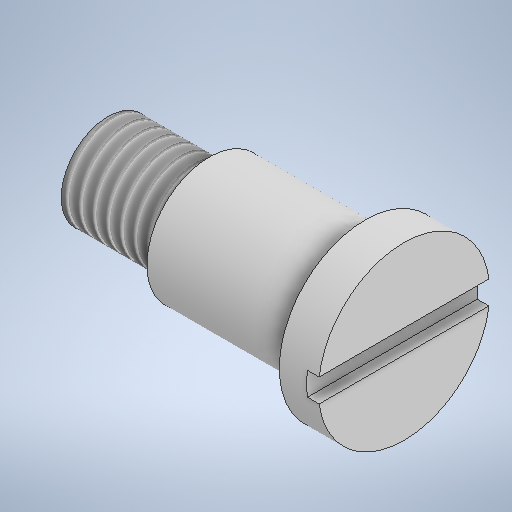
# Autodesk Inventor part: Pasador de acero
Saved by Autodesk Inventor 2025.3 (Build 293356030, 356C)
## iProperties
Created: 2025-08-17
Part Number: Pasador de acero
Material: Generic
Document SubType Name: Modeling
Designer: PC
Density: 1 g/cm^3
Appearance: Default
Author: PC
Autodesk Inventor part; units mm, degrees
ref_plane "YZ Plane" through (0, 0, 0) normal (1, 0, 0) x (0, 1, 0)
ref_plane "XZ Plane" through (0, 0, 0) normal (0, 1, 0) x (-1, 0, 0)
ref_plane "XY Plane" through (0, 0, 0) normal (0, 0, 1) x (1, 0, 0)
sketch "Sketch1" plane through (0, 0, 0) normal (0, 1, 0) x (-1, 0, 0)
  line L0 (0, 0) -> (-38, 0)
  line L1 (-38, 0) -> (-38, -11)
  line L2 (-38, -11) -> (-33, -11)
  line L3 (-33, -11) -> (-33, -8)
  line L4 (-13, -6) -> (0, -6)
  line L5 (0, -6) -> (0, 0)
  line L6 (-13, -6) -> (-13, -8)
  line L7 (-13, -8) -> (-33, -8)
  point P0 (0, -3)
  dimension "d0" = 38
  dimension "d1" = 11
  dimension "d2" = 5
  dimension "d3" = 38
  dimension "d4" = 6
  dimension "d5" = 8
  dimension "d6" = 20
  constraints: 16 end point, 5 perpendicular, 1 horizontal, 1 midpoint, 1 parallel
  measures "d0" distance of L0.start L0.end
  measures "d1" distance of L0.end L1.end
  measures "d2" distance of L1.end L2.end
  measures "d3" distance from line of point (0, -3) L1
  measures "d4" distance between parallel lines of L0 L4
  measures "d5" distance between parallel lines of L0 L7
  measures "d6" distance of L6.end L3.end
revolve "Revolution1" add sketch "Sketch1" angle 360 about axis through (0, 0, 0) along (1, 0, 0)
thread "Thread1" size "M12x1.75" class "6g" standard "ANSI Metric M Profile" length 13
sketch "Sketch2" plane through (38, 0, 0) normal (1, 0, 0) x (0, 0, -1)
  line L0 (-17.7504, 1.5) -> (19.4781, 1.5)
  line L1 (19.4781, 1.5) -> (19.4781, -1.5)
  line L2 (19.4781, -1.5) -> (-17.7504, -1.5)
  line L3 (-17.7504, -1.5) -> (-17.7504, 1.5)
  circle A0 centre (0, 0) radius 11 projected
  point P0 (10.8972, 1.5)
  point P1 (-10.8972, 1.5)
  point P2 (-10.8972, -1.5)
  point P3 (10.8972, -1.5)
  dimension "d10" = 3
  dimension "d11" = 1.5
  constraints: 8 end point, 2 parallel, 1 horizontal, 1 perpendicular
  measures "d10" distance of L0.end L1.end
  measures "d11" distance from line of A0.centre L0
extrude "Extrusion1" cut sketch "Sketch2" against normal blind 1.5 contours L0 A0 L2
body "Solid1"
